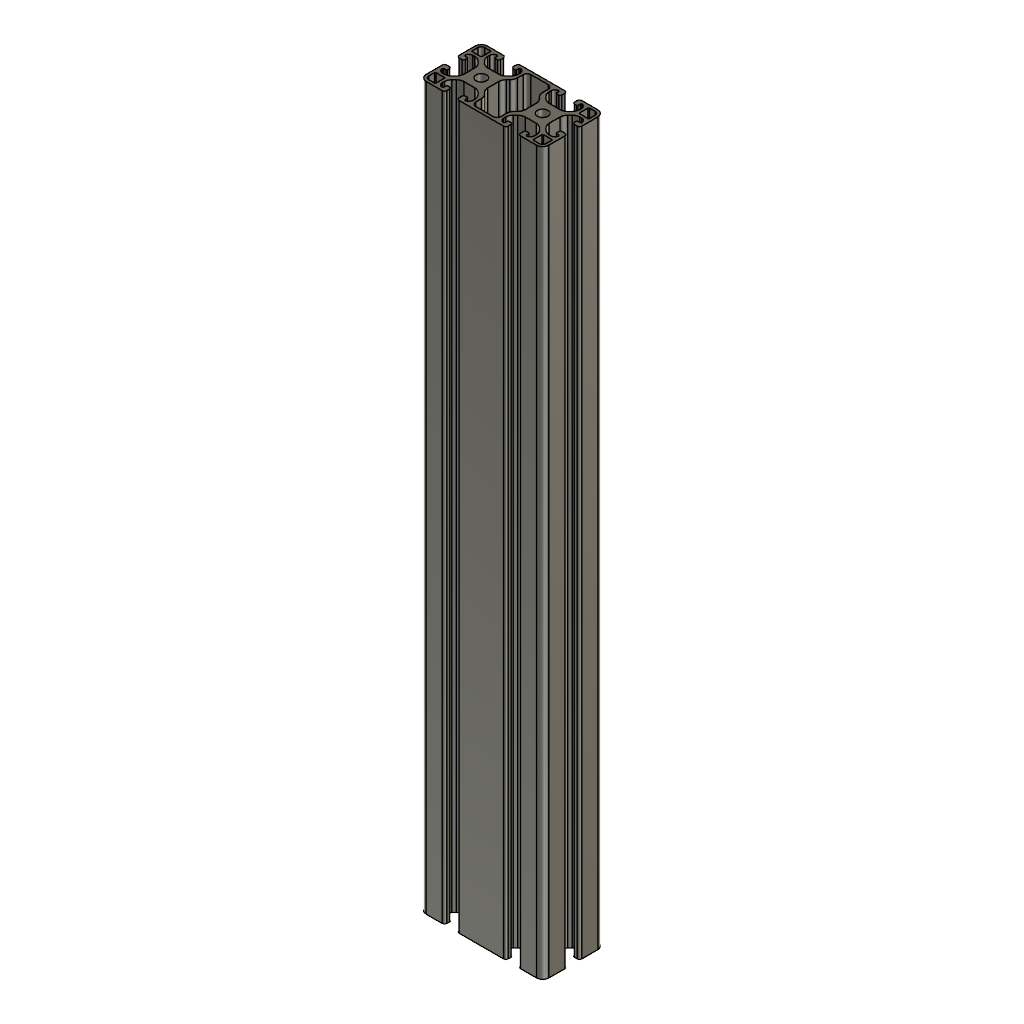
06-08 Alu Profile 80x40 L470 (Autodesk Fusion 360 design; units mm, degrees)
Autodesk Fusion 360 part; units mm, degrees
sketch "Sketch1" plane through (0, 0, 0) normal (0, 0, 1) x (1, 0, 0)
  line L0 (-5.7, 18) -> (5.7, 18)
  line L1 (14.5, 20) -> (-14.5, 20)
  line L2 (-14.5, -20) -> (14.5, -20)
  line L3 (-40, -5.5) -> (-40, -16)
  line L4 (-29.2145, -7.0931) -> (-30.6569, -8.5355)
  line L5 (-31.8, -12.3) -> (-31.8, -17.7)
  arc A0 (10.7855, -7.0931) -> (12.25, -3.5576) centre (7.25, -3.5576) ccw
  arc A1 (16.4424, -7.75) -> (12.9069, -9.2145) centre (16.4424, -12.75) ccw
  circle A2 centre (20, 0) radius 3.4
  arc A3 (9.6645, -8.2142) -> (8.2, -11.7497) centre (13.2, -11.7497) ccw
  line L6 (30, 15.5) -> (30, 14.1924)
  arc A4 (-15, -15.5) -> (-16, -16.5) centre (-15, -16.5) ccw
  line L7 (-5.7, 18) -> (5.7, 18)
  line L8 (-16, -16.5) -> (-16, -18.5)
  line L9 (-8.2, -15.5) -> (-8.2, -11.7497)
  arc A5 (-13, -17.5) -> (-12.5, -18) centre (-12.5, -17.5) ccw
  line L10 (-13, -17.5) -> (-13, -16)
  arc A6 (-8.2, -15.5) -> (-5.7, -18) centre (-5.7, -15.5) ccw
  arc A7 (14.5, -20) -> (16, -18.5) centre (14.5, -18.5) ccw
  arc A8 (16, -16.5) -> (15, -15.5) centre (15, -16.5) ccw
  arc A9 (13.5, -15.5) -> (13, -16) centre (13.5, -16) ccw
  line L11 (-9.6645, -8.2142) -> (-10.7855, -7.0931)
  arc A10 (27, -16) -> (26.5, -15.5) centre (26.5, -16) ccw
  arc A11 (-12.25, -3.5576) -> (-10.7855, -7.0931) centre (-7.25, -3.5576) ccw
  line L12 (-40, -5.5) -> (-40, -16)
  arc A12 (27, -17.5) -> (27.5, -18) centre (27.5, -17.5) ccw
  line L13 (-29.2145, -7.0931) -> (-30.6569, -8.5355)
  arc A13 (-11.4645, 10.6569) -> (-10, 14.1924) centre (-15, 14.1924) ccw
  arc A14 (-14.5, 20) -> (-16, 18.5) centre (-14.5, 18.5) ccw
  arc A15 (-12.9069, -9.2145) -> (-16.4424, -7.75) centre (-16.4424, -12.75) ccw
  line L14 (23.5576, 7.75) -> (16.4424, 7.75)
  line L15 (-10, -14.1924) -> (-10, -15.5)
  arc A16 (24, -18.5) -> (25.5, -20) centre (25.5, -18.5) ccw
  arc A17 (-12.5, 18) -> (-13, 17.5) centre (-12.5, 17.5) ccw
  arc A18 (27.5, -18) -> (30, -15.5) centre (27.5, -15.5) ccw
  line L16 (-12.25, -3.5576) -> (-12.25, 3.5576)
  arc A19 (35.5, 5) -> (36.5, 4) centre (36.5, 5) ccw
  arc A20 (-8.2, -15.5) -> (-5.7, -18) centre (-5.7, -15.5) ccw
  arc A21 (25, -15.5) -> (24, -16.5) centre (25, -16.5) ccw
  line L17 (38.5, -4) -> (36.5, -4)
  arc A22 (-12.25, -3.5576) -> (-10.7855, -7.0931) centre (-7.25, -3.5576) ccw
  arc A23 (-16, -18.5) -> (-14.5, -20) centre (-14.5, -18.5) ccw
  arc A24 (38.2, 16) -> (36, 18.2) centre (36, 16) ccw
  line L18 (-35.5, 10) -> (-34.1924, 10)
  line L19 (32.3, 18.2) -> (36, 18.2)
  arc A25 (-8.2, -11.7497) -> (-9.6645, -8.2142) centre (-13.2, -11.7497) ccw
  arc A26 (36, 7) -> (35.5, 6.5) centre (36, 6.5) ccw
  arc A27 (-16, 16.5) -> (-15, 15.5) centre (-15, 16.5) ccw
  arc A28 (-12.5, -18) -> (-10, -15.5) centre (-12.5, -15.5) ccw
  arc A29 (-13.5, 15.5) -> (-13, 16) centre (-13.5, 16) ccw
  arc A30 (31.8, 12.3) -> (32.3, 11.8) centre (32.3, 12.3) ccw
  line L20 (-23.5576, -7.75) -> (-16.4424, -7.75)
  arc A31 (37.7, 11.8) -> (38.2, 12.3) centre (37.7, 12.3) ccw
  line L21 (-12.9069, -9.2145) -> (-11.4645, -10.6569)
  line L22 (10.7855, -7.0931) -> (9.6645, -8.2142)
  arc A32 (-37.5, -7) -> (-38, -7.5) centre (-37.5, -7.5) ccw
  line L23 (23.5576, 7.75) -> (16.4424, 7.75)
  line L24 (30.6569, -8.5355) -> (29.2145, -7.0931)
  line L25 (-37.5, -7) -> (-36, -7)
  arc A33 (-34.1924, -10) -> (-30.6569, -8.5355) centre (-34.1924, -5) ccw
  line L26 (-30, -15.5) -> (-30, -14.1924)
  line L27 (-23.5576, -7.75) -> (-16.4424, -7.75)
  arc A34 (-38.2, -16) -> (-36, -18.2) centre (-36, -16) ccw
  line L28 (27.0931, -9.2145) -> (28.5355, -10.6569)
  arc A35 (-35.5, -5) -> (-36.5, -4) centre (-36.5, -5) ccw
  line L29 (16, -18.5) -> (16, -16.5)
  line L30 (5.7, -18) -> (-5.7, -18)
  arc A36 (13, 16) -> (13.5, 15.5) centre (13.5, 16) ccw
  line L31 (-38.5, 4) -> (-36.5, 4)
  arc A37 (10, -15.5) -> (12.5, -18) centre (12.5, -15.5) ccw
  arc A38 (15, 15.5) -> (16, 16.5) centre (15, 16.5) ccw
  arc A39 (5.7, -18) -> (8.2, -15.5) centre (5.7, -15.5) ccw
  arc A40 (16, 18.5) -> (14.5, 20) centre (14.5, 18.5) ccw
  arc A41 (-36, -7) -> (-35.5, -6.5) centre (-36, -6.5) ccw
  arc A42 (-29.2145, -7.0931) -> (-27.75, -3.5576) centre (-32.75, -3.5576) ccw
  circle A43 centre (-20, 0) radius 3.4
  arc A44 (12.5, -18) -> (13, -17.5) centre (12.5, -17.5) ccw
  arc A45 (-23.5576, -7.75) -> (-27.0931, -9.2145) centre (-23.5576, -12.75) ccw
  arc A46 (23.5576, 7.75) -> (27.0931, 9.2145) centre (23.5576, 12.75) ccw
  line L32 (-37.7, -11.8) -> (-32.3, -11.8)
  line L33 (27, -17.5) -> (27, -16)
  arc A47 (-16.4424, 7.75) -> (-12.9069, 9.2145) centre (-16.4424, 12.75) ccw
  arc A48 (11.4645, -10.6569) -> (10, -14.1924) centre (15, -14.1924) ccw
  line L34 (15, -15.5) -> (13.5, -15.5)
  line L35 (-11.4645, 10.6569) -> (-12.9069, 9.2145)
  line L36 (-16, 18.5) -> (-16, 16.5)
  line L37 (-16, -16.5) -> (-16, -18.5)
  arc A49 (34.1924, 10) -> (30.6569, 8.5355) centre (34.1924, 5) ccw
  line L38 (-36, -20) -> (-25.5, -20)
  line L39 (-38.2, -16) -> (-38.2, -12.3)
  line L40 (10, -15.5) -> (10, -14.1924)
  line L41 (-25, -15.5) -> (-26.5, -15.5)
  line L42 (-13, -17.5) -> (-13, -16)
  line L43 (-28.5355, -10.6569) -> (-27.0931, -9.2145)
  line L44 (8.2, -11.7497) -> (8.2, -15.5)
  arc A50 (-9.6645, 8.2142) -> (-8.2, 11.7497) centre (-13.2, 11.7497) ccw
  line L45 (30, -14.1924) -> (30, -15.5)
  line L46 (-13.5, -15.5) -> (-15, -15.5)
  line L47 (14.5, 20) -> (-14.5, 20)
  arc A51 (-10.7855, 7.0931) -> (-12.25, 3.5576) centre (-7.25, 3.5576) ccw
  arc A52 (-37.7, -11.8) -> (-38.2, -12.3) centre (-37.7, -12.3) ccw
  arc A53 (13, 17.5) -> (12.5, 18) centre (12.5, 17.5) ccw
  arc A54 (-32.3, 11.8) -> (-31.8, 12.3) centre (-32.3, 12.3) ccw
  line L48 (37.5, 7) -> (36, 7)
  arc A55 (-28.5355, -10.6569) -> (-30, -14.1924) centre (-25, -14.1924) ccw
  arc A56 (-27.75, 3.5576) -> (-29.2145, 7.0931) centre (-32.75, 3.5576) ccw
  line L49 (-30.6569, 8.5355) -> (-29.2145, 7.0931)
  arc A57 (12.5, -18) -> (13, -17.5) centre (12.5, -17.5) ccw
  line L50 (-25.5, 20) -> (-36, 20)
  line L51 (12.9069, 9.2145) -> (11.4645, 10.6569)
  line L52 (-36, 18.2) -> (-32.3, 18.2)
  line L53 (-37.7, -11.8) -> (-32.3, -11.8)
  line L54 (-10, -14.1924) -> (-10, -15.5)
  line L55 (9.6645, 8.2142) -> (10.7855, 7.0931)
  line L56 (5.7, -18) -> (-5.7, -18)
  arc A58 (-31.8, -12.3) -> (-32.3, -11.8) centre (-32.3, -12.3) ccw
  line L57 (-27.75, 3.5576) -> (-27.75, -3.5576)
  line L58 (11.4645, -10.6569) -> (12.9069, -9.2145)
  line L59 (-31.8, 17.7) -> (-31.8, 12.3)
  arc A59 (-27.0931, 9.2145) -> (-23.5576, 7.75) centre (-23.5576, 12.75) ccw
  arc A60 (-36, -7) -> (-35.5, -6.5) centre (-36, -6.5) ccw
  arc A61 (-29.2145, -7.0931) -> (-27.75, -3.5576) centre (-32.75, -3.5576) ccw
  arc A62 (-31.8, 17.7) -> (-32.3, 18.2) centre (-32.3, 17.7) ccw
  arc A63 (13, 16) -> (13.5, 15.5) centre (13.5, 16) ccw
  arc A64 (-27.0931, 9.2145) -> (-23.5576, 7.75) centre (-23.5576, 12.75) ccw
  arc A65 (31.8, -17.7) -> (32.3, -18.2) centre (32.3, -17.7) ccw
  line L60 (-31.8, 17.7) -> (-31.8, 12.3)
  arc A66 (-40, 5.5) -> (-38.5, 4) centre (-38.5, 5.5) ccw
  arc A67 (36, -18.2) -> (38.2, -16) centre (36, -16) ccw
  line L61 (16.4424, -7.75) -> (23.5576, -7.75)
  arc A68 (37.5, 7) -> (38, 7.5) centre (37.5, 7.5) ccw
  arc A69 (10, -15.5) -> (12.5, -18) centre (12.5, -15.5) ccw
  arc A70 (38, 7.5) -> (35.5, 10) centre (35.5, 7.5) ccw
  line L62 (10.7855, -7.0931) -> (9.6645, -8.2142)
  arc A71 (-32.3, -18.2) -> (-31.8, -17.7) centre (-32.3, -17.7) ccw
  arc A72 (5.7, -18) -> (8.2, -15.5) centre (5.7, -15.5) ccw
  arc A73 (-35.5, 6.5) -> (-36, 7) centre (-36, 6.5) ccw
  line L63 (35.5, 6.5) -> (35.5, 5)
  arc A74 (35.5, -10) -> (38, -7.5) centre (35.5, -7.5) ccw
  line L64 (-27.0931, 9.2145) -> (-28.5355, 10.6569)
  line L65 (-26.5, 15.5) -> (-25, 15.5)
  arc A75 (38.2, -12.3) -> (37.7, -11.8) centre (37.7, -12.3) ccw
  arc A76 (14.5, -20) -> (16, -18.5) centre (14.5, -18.5) ccw
  arc A77 (-36, 18.2) -> (-38.2, 16) centre (-36, 16) ccw
  arc A78 (-25.5, -20) -> (-24, -18.5) centre (-25.5, -18.5) ccw
  arc A79 (-38.2, 12.3) -> (-37.7, 11.8) centre (-37.7, 12.3) ccw
  arc A80 (36.5, -4) -> (35.5, -5) centre (36.5, -5) ccw
  arc A81 (-36.5, 4) -> (-35.5, 5) centre (-36.5, 5) ccw
  arc A82 (35.5, -6.5) -> (36, -7) centre (36, -6.5) ccw
  line L66 (-40, 16) -> (-40, 5.5)
  line L67 (38.2, -12.3) -> (38.2, -16)
  arc A83 (-24, -16.5) -> (-25, -15.5) centre (-25, -16.5) ccw
  arc A84 (-26.5, -15.5) -> (-27, -16) centre (-26.5, -16) ccw
  arc A85 (8.2, 11.7497) -> (9.6645, 8.2142) centre (13.2, 11.7497) ccw
  line L68 (28.5355, 10.6569) -> (27.0931, 9.2145)
  arc A86 (-38, -7.5) -> (-35.5, -10) centre (-35.5, -7.5) ccw
  line L69 (11.4645, -10.6569) -> (12.9069, -9.2145)
  line L70 (13.5, 15.5) -> (15, 15.5)
  arc A87 (12.5, 18) -> (10, 15.5) centre (12.5, 15.5) ccw
  arc A88 (27.75, -3.5576) -> (29.2145, -7.0931) centre (32.75, -3.5576) ccw
  arc A89 (-30, -15.5) -> (-27.5, -18) centre (-27.5, -15.5) ccw
  arc A90 (-38.5, -4) -> (-40, -5.5) centre (-38.5, -5.5) ccw
  line L71 (-35.5, -6.5) -> (-35.5, -5)
  line L72 (40, 5.5) -> (40, 16)
  arc A91 (10, 14.1924) -> (11.4645, 10.6569) centre (15, 14.1924) ccw
  line L73 (16, 16.5) -> (16, 18.5)
  line L74 (-36.5, -4) -> (-38.5, -4)
  arc A92 (-25.5, -20) -> (-24, -18.5) centre (-25.5, -18.5) ccw
  line L75 (-24, -18.5) -> (-24, -16.5)
  line L76 (-40, 16) -> (-40, 5.5)
  line L77 (29.2145, 7.0931) -> (30.6569, 8.5355)
  arc A93 (-40, -16) -> (-36, -20) centre (-36, -16) ccw
  line L78 (-32.3, -18.2) -> (-36, -18.2)
  arc A94 (12.9069, 9.2145) -> (16.4424, 7.75) centre (16.4424, 12.75) ccw
  arc A95 (-30, 14.1924) -> (-28.5355, 10.6569) centre (-25, 14.1924) ccw
  line L79 (37.5, 7) -> (36, 7)
  line L80 (36, -18.2) -> (32.3, -18.2)
  arc A96 (30, 15.5) -> (27.5, 18) centre (27.5, 15.5) ccw
  arc A97 (23.5576, 7.75) -> (27.0931, 9.2145) centre (23.5576, 12.75) ccw
  line L81 (-35.5, 5) -> (-35.5, 6.5)
  arc A98 (28.5355, 10.6569) -> (30, 14.1924) centre (25, 14.1924) ccw
  line L82 (28.5355, 10.6569) -> (27.0931, 9.2145)
  arc A99 (25.5, 20) -> (24, 18.5) centre (25.5, 18.5) ccw
  line L83 (-36.5, -4) -> (-38.5, -4)
  line L84 (25, 15.5) -> (26.5, 15.5)
  line L85 (-31.8, -12.3) -> (-31.8, -17.7)
  line L86 (-30, -15.5) -> (-30, -14.1924)
  line L87 (-26.5, 15.5) -> (-25, 15.5)
  line L88 (36, -7) -> (37.5, -7)
  line L89 (40, -16) -> (40, -5.5)
  arc A100 (-38, 7.5) -> (-37.5, 7) centre (-37.5, 7.5) ccw
  line L90 (-24, 16.5) -> (-24, 18.5)
  line L91 (24, 18.5) -> (24, 16.5)
  line L92 (-30, 14.1924) -> (-30, 15.5)
  arc A101 (38, 7.5) -> (35.5, 10) centre (35.5, 7.5) ccw
  arc A102 (27.75, -3.5576) -> (29.2145, -7.0931) centre (32.75, -3.5576) ccw
  arc A103 (30, -14.1924) -> (28.5355, -10.6569) centre (25, -14.1924) ccw
  arc A104 (27, -17.5) -> (27.5, -18) centre (27.5, -17.5) ccw
  arc A105 (-25, 15.5) -> (-24, 16.5) centre (-25, 16.5) ccw
  line L93 (36.5, 4) -> (38.5, 4)
  arc A106 (30.6569, -8.5355) -> (34.1924, -10) centre (34.1924, -5) ccw
  arc A107 (36.5, -4) -> (35.5, -5) centre (36.5, -5) ccw
  arc A108 (26.5, 15.5) -> (27, 16) centre (26.5, 16) ccw
  arc A109 (27, -16) -> (26.5, -15.5) centre (26.5, -16) ccw
  line L94 (37.7, 11.8) -> (32.3, 11.8)
  line L95 (-27, -16) -> (-27, -17.5)
  line L96 (38.2, 16) -> (38.2, 12.3)
  arc A110 (38, -7.5) -> (37.5, -7) centre (37.5, -7.5) ccw
  line L97 (-24, 16.5) -> (-24, 18.5)
  arc A111 (32.3, 18.2) -> (31.8, 17.7) centre (32.3, 17.7) ccw
  line L98 (30, 15.5) -> (30, 14.1924)
  arc A112 (-40, 5.5) -> (-38.5, 4) centre (-38.5, 5.5) ccw
  arc A113 (-36, 18.2) -> (-38.2, 16) centre (-36, 16) ccw
  line L99 (-35.5, -6.5) -> (-35.5, -5)
  arc A114 (38.2, 16) -> (36, 18.2) centre (36, 16) ccw
  line L100 (-37.5, -7) -> (-36, -7)
  line L101 (35.5, 6.5) -> (35.5, 5)
  line L102 (31.8, 12.3) -> (31.8, 17.7)
  line L103 (-35.5, 10) -> (-34.1924, 10)
  arc A115 (-36, 20) -> (-40, 16) centre (-36, 16) ccw
  arc A116 (-24, 18.5) -> (-25.5, 20) centre (-25.5, 18.5) ccw
  arc A117 (-27, 17.5) -> (-27.5, 18) centre (-27.5, 17.5) ccw
  arc A118 (-27, 16) -> (-26.5, 15.5) centre (-26.5, 16) ccw
  arc A119 (27.5, 18) -> (27, 17.5) centre (27.5, 17.5) ccw
  arc A120 (-10, -14.1924) -> (-11.4645, -10.6569) centre (-15, -14.1924) ccw
  arc A121 (-23.5576, -7.75) -> (-27.0931, -9.2145) centre (-23.5576, -12.75) ccw
  line L104 (-27.75, 3.5576) -> (-27.75, -3.5576)
  arc A122 (-27.5, -18) -> (-27, -17.5) centre (-27.5, -17.5) ccw
  line L105 (16, 16.5) -> (16, 18.5)
  arc A123 (-24, -16.5) -> (-25, -15.5) centre (-25, -16.5) ccw
  line L106 (13.5, 15.5) -> (15, 15.5)
  line L107 (34.1924, 10) -> (35.5, 10)
  arc A124 (30, 15.5) -> (27.5, 18) centre (27.5, 15.5) ccw
  line L108 (-28.5355, -10.6569) -> (-27.0931, -9.2145)
  line L109 (35.5, -5) -> (35.5, -6.5)
  line L110 (40, -16) -> (40, -5.5)
  arc A125 (-38.2, -16) -> (-36, -18.2) centre (-36, -16) ccw
  line L111 (38.2, 16) -> (38.2, 12.3)
  line L112 (15, -15.5) -> (13.5, -15.5)
  arc A126 (-30, -15.5) -> (-27.5, -18) centre (-27.5, -15.5) ccw
  arc A127 (25.5, 20) -> (24, 18.5) centre (25.5, 18.5) ccw
  line L113 (13, -16) -> (13, -17.5)
  line L114 (10, -15.5) -> (10, -14.1924)
  arc A128 (32.3, 18.2) -> (31.8, 17.7) centre (32.3, 17.7) ccw
  line L115 (37.7, 11.8) -> (32.3, 11.8)
  arc A129 (27.5, 18) -> (27, 17.5) centre (27.5, 17.5) ccw
  line L116 (31.8, 12.3) -> (31.8, 17.7)
  arc A130 (26.5, 15.5) -> (27, 16) centre (26.5, 16) ccw
  arc A131 (-26.5, -15.5) -> (-27, -16) centre (-26.5, -16) ccw
  line L117 (16, -18.5) -> (16, -16.5)
  line L118 (36, -7) -> (37.5, -7)
  arc A132 (24, 16.5) -> (25, 15.5) centre (25, 16.5) ccw
  arc A133 (16.4424, -7.75) -> (12.9069, -9.2145) centre (16.4424, -12.75) ccw
  arc A134 (16, -16.5) -> (15, -15.5) centre (15, -16.5) ccw
  arc A135 (28.5355, 10.6569) -> (30, 14.1924) centre (25, 14.1924) ccw
  line L119 (-9.6645, -8.2142) -> (-10.7855, -7.0931)
  arc A136 (40, 16) -> (36, 20) centre (36, 16) ccw
  arc A137 (30.6569, -8.5355) -> (34.1924, -10) centre (34.1924, -5) ccw
  line L120 (-27.0931, 9.2145) -> (-28.5355, 10.6569)
  line L121 (12.25, 3.5576) -> (12.25, -3.5576)
  arc A138 (8.2, 11.7497) -> (9.6645, 8.2142) centre (13.2, 11.7497) ccw
  arc A139 (13.5, -15.5) -> (13, -16) centre (13.5, -16) ccw
  line L122 (35.5, -10) -> (34.1924, -10)
  line L123 (-25.5, 20) -> (-36, 20)
  arc A140 (11.4645, -10.6569) -> (10, -14.1924) centre (15, -14.1924) ccw
  arc A141 (-30.6569, 8.5355) -> (-34.1924, 10) centre (-34.1924, 5) ccw
  arc A142 (9.6645, -8.2142) -> (8.2, -11.7497) centre (13.2, -11.7497) ccw
  arc A143 (12.5, 18) -> (10, 15.5) centre (12.5, 15.5) ccw
  line L124 (-8.2, -15.5) -> (-8.2, -11.7497)
  arc A144 (-27.5, -18) -> (-27, -17.5) centre (-27.5, -17.5) ccw
  line L125 (12.9069, 9.2145) -> (11.4645, 10.6569)
  line L126 (13, 17.5) -> (13, 16)
  arc A145 (-32.3, -18.2) -> (-31.8, -17.7) centre (-32.3, -17.7) ccw
  line L127 (12.25, 3.5576) -> (12.25, -3.5576)
  line L128 (-34.1924, -10) -> (-35.5, -10)
  arc A146 (12.25, 3.5576) -> (10.7855, 7.0931) centre (7.25, 3.5576) ccw
  arc A147 (-28.5355, -10.6569) -> (-30, -14.1924) centre (-25, -14.1924) ccw
  arc A148 (30, -14.1924) -> (28.5355, -10.6569) centre (25, -14.1924) ccw
  line L129 (27.75, -3.5576) -> (27.75, 3.5576)
  arc A149 (-31.8, -12.3) -> (-32.3, -11.8) centre (-32.3, -12.3) ccw
  arc A150 (-12.9069, -9.2145) -> (-16.4424, -7.75) centre (-16.4424, -12.75) ccw
  arc A151 (8.2, 15.5) -> (5.7, 18) centre (5.7, 15.5) ccw
  line L130 (16.4424, -7.75) -> (23.5576, -7.75)
  arc A152 (27.0931, -9.2145) -> (23.5576, -7.75) centre (23.5576, -12.75) ccw
  arc A153 (27.0931, -9.2145) -> (23.5576, -7.75) centre (23.5576, -12.75) ccw
  line L131 (36, 20) -> (25.5, 20)
  line L132 (-11.4645, 10.6569) -> (-12.9069, 9.2145)
  arc A154 (38.2, -12.3) -> (37.7, -11.8) centre (37.7, -12.3) ccw
  line L133 (32.3, 18.2) -> (36, 18.2)
  line L134 (-13, 16) -> (-13, 17.5)
  line L135 (10, 14.1924) -> (10, 15.5)
  line L136 (-10.7855, 7.0931) -> (-9.6645, 8.2142)
  arc A155 (-5.7, 18) -> (-8.2, 15.5) centre (-5.7, 15.5) ccw
  arc A156 (12.9069, 9.2145) -> (16.4424, 7.75) centre (16.4424, 12.75) ccw
  arc A157 (-34.1924, -10) -> (-30.6569, -8.5355) centre (-34.1924, -5) ccw
  arc A158 (36, -18.2) -> (38.2, -16) centre (36, -16) ccw
  arc A159 (36, -20) -> (40, -16) centre (36, -16) ccw
  line L137 (-16, 18.5) -> (-16, 16.5)
  arc A160 (-38, -7.5) -> (-35.5, -10) centre (-35.5, -7.5) ccw
  line L138 (-30, 14.1924) -> (-30, 15.5)
  arc A161 (-24, 18.5) -> (-25.5, 20) centre (-25.5, 18.5) ccw
  arc A162 (36, 7) -> (35.5, 6.5) centre (36, 6.5) ccw
  line L139 (27, -17.5) -> (27, -16)
  line L140 (34.1924, 10) -> (35.5, 10)
  arc A163 (31.8, 12.3) -> (32.3, 11.8) centre (32.3, 12.3) ccw
  line L141 (-15, 15.5) -> (-13.5, 15.5)
  arc A164 (40, 16) -> (36, 20) centre (36, 16) ccw
  arc A165 (-35.5, 10) -> (-38, 7.5) centre (-35.5, 7.5) ccw
  arc A166 (-10.7855, 7.0931) -> (-12.25, 3.5576) centre (-7.25, 3.5576) ccw
  line L142 (26.5, -15.5) -> (25, -15.5)
  arc A167 (25, -15.5) -> (24, -16.5) centre (25, -16.5) ccw
  arc A168 (35.5, -10) -> (38, -7.5) centre (35.5, -7.5) ccw
  arc A169 (-11.4645, 10.6569) -> (-10, 14.1924) centre (-15, 14.1924) ccw
  line L143 (-8.2, 11.7497) -> (-8.2, 15.5)
  arc A170 (24, 16.5) -> (25, 15.5) centre (25, 16.5) ccw
  line L144 (27.0931, -9.2145) -> (28.5355, -10.6569)
  line L145 (38.2, -12.3) -> (38.2, -16)
  line L146 (30.6569, -8.5355) -> (29.2145, -7.0931)
  line L147 (32.3, -11.8) -> (37.7, -11.8)
  arc A171 (35.5, -6.5) -> (36, -7) centre (36, -6.5) ccw
  arc A172 (-16.4424, 7.75) -> (-12.9069, 9.2145) centre (-16.4424, 12.75) ccw
  arc A173 (-14.5, 20) -> (-16, 18.5) centre (-14.5, 18.5) ccw
  line L148 (27, 16) -> (27, 17.5)
  line L149 (-25, -15.5) -> (-26.5, -15.5)
  line L150 (-30.6569, 8.5355) -> (-29.2145, 7.0931)
  arc A174 (32.3, -11.8) -> (31.8, -12.3) centre (32.3, -12.3) ccw
  line L151 (-34.1924, -10) -> (-35.5, -10)
  arc A175 (-27, 17.5) -> (-27.5, 18) centre (-27.5, 17.5) ccw
  line L152 (-27, 17.5) -> (-27, 16)
  line L153 (40, 5.5) -> (40, 16)
  arc A176 (-9.6645, 8.2142) -> (-8.2, 11.7497) centre (-13.2, 11.7497) ccw
  arc A177 (-10, 15.5) -> (-12.5, 18) centre (-12.5, 15.5) ccw
  arc A178 (29.2145, 7.0931) -> (27.75, 3.5576) centre (32.75, 3.5576) ccw
  line L154 (30, -14.1924) -> (30, -15.5)
  arc A179 (38.5, 4) -> (40, 5.5) centre (38.5, 5.5) ccw
  arc A180 (24, -18.5) -> (25.5, -20) centre (25.5, -18.5) ccw
  arc A181 (-13.5, 15.5) -> (-13, 16) centre (-13.5, 16) ccw
  line L155 (29.2145, 7.0931) -> (30.6569, 8.5355)
  arc A182 (-12.5, 18) -> (-13, 17.5) centre (-12.5, 17.5) ccw
  line L156 (-38.2, -16) -> (-38.2, -12.3)
  arc A183 (27.5, -18) -> (30, -15.5) centre (27.5, -15.5) ccw
  arc A184 (37.7, 11.8) -> (38.2, 12.3) centre (37.7, 12.3) ccw
  arc A185 (31.8, -17.7) -> (32.3, -18.2) centre (32.3, -17.7) ccw
  arc A186 (-27, 16) -> (-26.5, 15.5) centre (-26.5, 16) ccw
  line L157 (-32.3, -18.2) -> (-36, -18.2)
  line L158 (31.8, -17.7) -> (31.8, -12.3)
  line L159 (-36, 7) -> (-37.5, 7)
  line L160 (24, -16.5) -> (24, -18.5)
  arc A187 (34.1924, 10) -> (30.6569, 8.5355) centre (34.1924, 5) ccw
  arc A188 (-27.5, 18) -> (-30, 15.5) centre (-27.5, 15.5) ccw
  line L161 (35.5, -10) -> (34.1924, -10)
  line L162 (25.5, -20) -> (36, -20)
  arc A189 (35.5, 5) -> (36.5, 4) centre (36.5, 5) ccw
  line L163 (35.5, -5) -> (35.5, -6.5)
  arc A190 (37.5, 7) -> (38, 7.5) centre (37.5, 7.5) ccw
  line L164 (-38.5, 4) -> (-36.5, 4)
  arc A191 (-37.7, -11.8) -> (-38.2, -12.3) centre (-37.7, -12.3) ccw
  line L165 (8.2, -11.7497) -> (8.2, -15.5)
  line L166 (36.5, 4) -> (38.5, 4)
  arc A192 (-35.5, 6.5) -> (-36, 7) centre (-36, 6.5) ccw
  arc A193 (-36.5, 4) -> (-35.5, 5) centre (-36.5, 5) ccw
  arc A194 (-37.5, -7) -> (-38, -7.5) centre (-37.5, -7.5) ccw
  arc A195 (38, -7.5) -> (37.5, -7) centre (37.5, -7.5) ccw
  arc A196 (-38.5, -4) -> (-40, -5.5) centre (-38.5, -5.5) ccw
  arc A197 (15, 15.5) -> (16, 16.5) centre (15, 16.5) ccw
  arc A198 (-40, -16) -> (-36, -20) centre (-36, -16) ccw
  line L167 (-24, -18.5) -> (-24, -16.5)
  arc A199 (-35.5, 10) -> (-38, 7.5) centre (-35.5, 7.5) ccw
  line L168 (-32.3, 11.8) -> (-37.7, 11.8)
  arc A200 (-35.5, -5) -> (-36.5, -4) centre (-36.5, -5) ccw
  arc A201 (32.3, -11.8) -> (31.8, -12.3) centre (32.3, -12.3) ccw
  arc A202 (38.5, 4) -> (40, 5.5) centre (38.5, 5.5) ccw
  arc A203 (12.25, 3.5576) -> (10.7855, 7.0931) centre (7.25, 3.5576) ccw
  arc A204 (-27.5, 18) -> (-30, 15.5) centre (-27.5, 15.5) ccw
  line L169 (36, -18.2) -> (32.3, -18.2)
  arc A205 (-38, 7.5) -> (-37.5, 7) centre (-37.5, 7.5) ccw
  arc A206 (8.2, 15.5) -> (5.7, 18) centre (5.7, 15.5) ccw
  line L170 (-16.4424, 7.75) -> (-23.5576, 7.75)
  arc A207 (-30.6569, 8.5355) -> (-34.1924, 10) centre (-34.1924, 5) ccw
  line L171 (27.75, -3.5576) -> (27.75, 3.5576)
  arc A208 (-32.3, 11.8) -> (-31.8, 12.3) centre (-32.3, 12.3) ccw
  line L172 (-32.3, 11.8) -> (-37.7, 11.8)
  arc A209 (36, -20) -> (40, -16) centre (36, -16) ccw
  arc A210 (40, -5.5) -> (38.5, -4) centre (38.5, -5.5) ccw
  arc A211 (-38.2, 12.3) -> (-37.7, 11.8) centre (-37.7, 12.3) ccw
  arc A212 (10.7855, -7.0931) -> (12.25, -3.5576) centre (7.25, -3.5576) ccw
  line L173 (-38.2, 12.3) -> (-38.2, 16)
  arc A213 (-31.8, 17.7) -> (-32.3, 18.2) centre (-32.3, 17.7) ccw
  line L174 (8.2, 15.5) -> (8.2, 11.7497)
  line L175 (31.8, -17.7) -> (31.8, -12.3)
  arc A214 (10, 14.1924) -> (11.4645, 10.6569) centre (15, 14.1924) ccw
  line L176 (-38.2, 12.3) -> (-38.2, 16)
  arc A215 (-36, 20) -> (-40, 16) centre (-36, 16) ccw
  line L177 (-27, 17.5) -> (-27, 16)
  arc A216 (13, 17.5) -> (12.5, 18) centre (12.5, 17.5) ccw
  line L178 (-36, 18.2) -> (-32.3, 18.2)
  arc A217 (40, -5.5) -> (38.5, -4) centre (38.5, -5.5) ccw
  line L179 (-10, 15.5) -> (-10, 14.1924)
  line L180 (32.3, -11.8) -> (37.7, -11.8)
  arc A218 (16, 18.5) -> (14.5, 20) centre (14.5, 18.5) ccw
  arc A219 (-25, 15.5) -> (-24, 16.5) centre (-25, 16.5) ccw
  line L181 (13, 17.5) -> (13, 16)
  arc A220 (-27.75, 3.5576) -> (-29.2145, 7.0931) centre (-32.75, 3.5576) ccw
  arc A221 (-16, 16.5) -> (-15, 15.5) centre (-15, 16.5) ccw
  line L182 (38.5, -4) -> (36.5, -4)
  arc A222 (-30, 14.1924) -> (-28.5355, 10.6569) centre (-25, 14.1924) ccw
  line L183 (-13, 16) -> (-13, 17.5)
  line L184 (-12.25, -3.5576) -> (-12.25, 3.5576)
  line L185 (24, -16.5) -> (24, -18.5)
  arc A223 (-13, -16) -> (-13.5, -15.5) centre (-13.5, -16) ccw
  arc A224 (-10, -14.1924) -> (-11.4645, -10.6569) centre (-15, -14.1924) ccw
  arc A225 (-13, -16) -> (-13.5, -15.5) centre (-13.5, -16) ccw
  line L186 (-10, 15.5) -> (-10, 14.1924)
  arc A226 (-12.5, -18) -> (-10, -15.5) centre (-12.5, -15.5) ccw
  line L187 (27, 16) -> (27, 17.5)
  line L188 (8.2, 15.5) -> (8.2, 11.7497)
  line L189 (-13.5, -15.5) -> (-15, -15.5)
  arc A227 (-8.2, -11.7497) -> (-9.6645, -8.2142) centre (-13.2, -11.7497) ccw
  arc A228 (-15, -15.5) -> (-16, -16.5) centre (-15, -16.5) ccw
  arc A229 (-13, -17.5) -> (-12.5, -18) centre (-12.5, -17.5) ccw
  line L190 (-36, 7) -> (-37.5, 7)
  line L191 (-12.9069, -9.2145) -> (-11.4645, -10.6569)
  arc A230 (-16, -18.5) -> (-14.5, -20) centre (-14.5, -18.5) ccw
  line L192 (-8.2, 11.7497) -> (-8.2, 15.5)
  line L193 (25.5, -20) -> (36, -20)
  line L194 (-36, -20) -> (-25.5, -20)
  line L195 (-27, -16) -> (-27, -17.5)
  arc A231 (29.2145, 7.0931) -> (27.75, 3.5576) centre (32.75, 3.5576) ccw
  line L196 (24, 18.5) -> (24, 16.5)
  line L197 (36, 20) -> (25.5, 20)
  line L198 (10, 14.1924) -> (10, 15.5)
  line L199 (9.6645, 8.2142) -> (10.7855, 7.0931)
  line L200 (26.5, -15.5) -> (25, -15.5)
  line L201 (13, -16) -> (13, -17.5)
  line L202 (-16.4424, 7.75) -> (-23.5576, 7.75)
  arc A232 (-5.7, 18) -> (-8.2, 15.5) centre (-5.7, 15.5) ccw
  line L203 (-15, 15.5) -> (-13.5, 15.5)
  line L204 (-35.5, 5) -> (-35.5, 6.5)
  line L205 (-14.5, -20) -> (14.5, -20)
  line L206 (25, 15.5) -> (26.5, 15.5)
  line L207 (-10.7855, 7.0931) -> (-9.6645, 8.2142)
  arc A233 (-10, 15.5) -> (-12.5, 18) centre (-12.5, 15.5) ccw
  dimension "d1" = 0
  dimension "d2" = 0
  dimension "d3" = 0
  dimension "d4" = 0
  dimension "d5" = 0
  dimension "d6" = 0
  measures "d1" distance of L127
  measures "d2" distance of L23
  measures "d3" distance of L115
  measures "d4" distance of L175
  measures "d5" distance of L60
  measures "d6" distance of L53
extrude "Extrude1" add sketch "Sketch1" along normal blind 470
